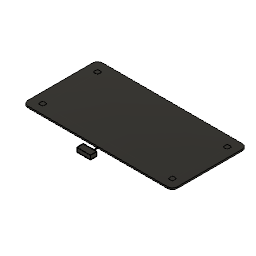
matt v2 (Autodesk Fusion 360 design; units mm, degrees)
part number: 2026-10-25-22-26-51-922
Autodesk Fusion 360 part; units mm, degrees
sketch "Boceto1" plane through (0, 0, 0) normal (0, 0, 1) x (1, 0, 0)
  arc A0 (1160, 0) -> (1200, 40) centre (1160, 40) ccw
  arc A1 (1200, 560) -> (1160, 600) centre (1160, 560) ccw
  arc A2 (40, 600) -> (0, 560) centre (40, 560) ccw
  arc A3 (0, 40) -> (40, 0) centre (40, 40) ccw
  line L0 (40, 0) -> (1160, 0)
  line L1 (1200, 40) -> (1200, 560)
  line L2 (1160, 600) -> (40, 600)
  line L3 (0, 560) -> (0, 40)
extrude "Extruir1" add sketch "Boceto1" along normal blind 12 makes body 1
ref_plane "PlanoDeObra1" through (0, 0, -1) normal (0, 0, 1) x (1, 0, 0)
sketch "Boceto2" plane through (0, 0, -1) normal (0, 0, 1) x (1, 0, 0)
  circle A0 centre (80, 80) radius 20
extrude "Extruir2" cut sketch "Boceto2" along normal blind 9 bodies 1
sketch "Boceto3" plane through (0, 0, -1) normal (0, 0, 1) x (1, 0, 0)
  circle A0 centre (1120, 80) radius 20
extrude "Extruir3" cut sketch "Boceto3" along normal blind 9 bodies 1
sketch "Boceto4" plane through (0, 0, -1) normal (0, 0, 1) x (1, 0, 0)
  circle A0 centre (80, 520) radius 20
extrude "Extruir4" cut sketch "Boceto4" along normal blind 9 bodies 1
sketch "Boceto5" plane through (0, 0, -1) normal (0, 0, 1) x (1, 0, 0)
  circle A0 centre (1120, 520) radius 20
extrude "Extruir5" cut sketch "Boceto5" along normal blind 9 bodies 1
sketch "Boceto6" plane through (0, 0, -1) normal (0, 0, 1) x (1, 0, 0)
  line L0 (80, 77) -> (1120, 77)
  line L1 (1120, 77) -> (1120, 83)
  line L2 (1120, 83) -> (80, 83)
  line L3 (80, 83) -> (80, 77)
extrude "Extruir6" cut sketch "Boceto6" along normal blind 5 bodies 1
sketch "Boceto7" plane through (0, 0, -1) normal (0, 0, 1) x (1, 0, 0)
  line L0 (77, 80) -> (83, 80)
  line L1 (83, 80) -> (83, 520)
  line L2 (83, 520) -> (77, 520)
  line L3 (77, 520) -> (77, 80)
extrude "Extruir7" cut sketch "Boceto7" along normal blind 5 bodies 1
sketch "Boceto8" plane through (0, 0, -1) normal (0, 0, 1) x (1, 0, 0)
  line L0 (1117, 80) -> (1123, 80)
  line L1 (1123, 80) -> (1123, 520)
  line L2 (1123, 520) -> (1117, 520)
  line L3 (1117, 520) -> (1117, 80)
extrude "Extruir8" cut sketch "Boceto8" along normal blind 5 bodies 1
sketch "Boceto9" plane through (0, 0, -1) normal (0, 0, 1) x (1, 0, 0)
  line L0 (597, -1) -> (603, -1)
  line L1 (603, -1) -> (603, 83)
  line L2 (603, 83) -> (597, 83)
  line L3 (597, 83) -> (597, -1)
extrude "Extruir9" cut sketch "Boceto9" along normal blind 5 bodies 1
sketch "Boceto10" plane through (0, 0, 0) normal (0, 0, 1) x (1, 0, 0)
  line L0 (544.5, -112.6) -> (655.5, -112.6)
  line L1 (655.5, -112.6) -> (655.5, -60)
  line L2 (655.5, -60) -> (544.5, -60)
  line L3 (544.5, -60) -> (544.5, -112.6)
extrude "Extruir10" add sketch "Boceto10" along normal blind 33.5 separate body makes body 2
ref_plane "PlanoDeObra2" through (0, 0, 2.5) normal (0, 0, 1) x (1, 0, 0)
sketch "Boceto11" plane through (0, 0, 2.5) normal (0, 0, 1) x (1, 0, 0)
  line L0 (547, -110.1) -> (653, -110.1)
  line L1 (653, -110.1) -> (653, -62.5)
  line L2 (653, -62.5) -> (547, -62.5)
  line L3 (547, -62.5) -> (547, -110.1)
extrude "Extruir11" cut sketch "Boceto11" along normal blind 32 bodies 2
ref_plane "PlanoDeObra3" through (0, 0, 33.5) normal (0, 0, 1) x (1, 0, 0)
sketch "Boceto12" plane through (0, 0, 33.5) normal (0, 0, 1) x (1, 0, 0)
  line L0 (544.5, -112.6) -> (655.5, -112.6)
  line L1 (655.5, -112.6) -> (655.5, -60)
  line L2 (655.5, -60) -> (544.5, -60)
  line L3 (544.5, -60) -> (544.5, -112.6)
extrude "Extruir12" add sketch "Boceto12" along normal blind 2.5 separate body makes body 3
sketch "Boceto13" plane through (0, 0, 2.5) normal (0, 0, 1) x (1, 0, 0)
  line L0 (597, -63.5) -> (603, -63.5)
  line L1 (603, -63.5) -> (603, -59)
  line L2 (603, -59) -> (597, -59)
  line L3 (597, -59) -> (597, -63.5)
extrude "Extruir13" cut sketch "Boceto13" along normal blind 6 bodies 2
ref_plane "PlanoDeObra4" through (0, 0, 0.5) normal (0, 0, 1) x (1, 0, 0)
sketch "Boceto14" plane through (0, 0, 0.5) normal (0, 0, 1) x (1, 0, 0)
  line L0 (597, -62.5) -> (603, -62.5)
  line L1 (603, -62.5) -> (603, 1)
  line L2 (603, 1) -> (597, 1)
  line L3 (597, 1) -> (597, -62.5)
extrude "Extruir14" add sketch "Boceto14" along normal blind 3.6 separate body makes body 4
sketch "Boceto15" plane through (0, 0, 0) normal (0, 0, 1) x (1, 0, 0)
  line L0 (63, 63) -> (97, 63)
  line L1 (97, 63) -> (97, 97)
  line L2 (97, 97) -> (63, 97)
  line L3 (63, 97) -> (63, 63)
extrude "Extruir15" add sketch "Boceto15" along normal blind 8 separate body makes body 5
sketch "Boceto16" plane through (0, 0, 0) normal (0, 0, 1) x (1, 0, 0)
  line L0 (1103, 63) -> (1137, 63)
  line L1 (1137, 63) -> (1137, 97)
  line L2 (1137, 97) -> (1103, 97)
  line L3 (1103, 97) -> (1103, 63)
extrude "Extruir16" add sketch "Boceto16" along normal blind 8 separate body makes body 6
sketch "Boceto17" plane through (0, 0, 0) normal (0, 0, 1) x (1, 0, 0)
  line L0 (63, 503) -> (97, 503)
  line L1 (97, 503) -> (97, 537)
  line L2 (97, 537) -> (63, 537)
  line L3 (63, 537) -> (63, 503)
extrude "Extruir17" add sketch "Boceto17" along normal blind 8 separate body makes body 7
sketch "Boceto18" plane through (0, 0, 0) normal (0, 0, 1) x (1, 0, 0)
  line L0 (1103, 503) -> (1137, 503)
  line L1 (1137, 503) -> (1137, 537)
  line L2 (1137, 537) -> (1103, 537)
  line L3 (1103, 537) -> (1103, 503)
extrude "Extruir18" add sketch "Boceto18" along normal blind 8 separate body makes body 8
named bodies: "Mat", "Modulo_electronica", "Tapa_modulo", "Cable", "Celda_1", "Celda_2", "Celda_3", "Celda_4"
